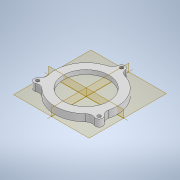
# Autodesk Inventor part: PalmClosure
Saved by Autodesk Inventor 2021 (Build 250183000, 183)
## iProperties
Created: 2026-04-22
Part Number: PalmClosure
Material: Generic
Document SubType Name: Modeling
Designer: Admin
Density: 1 g/cm^3
Appearance: Default
Author: Admin
Autodesk Inventor part; units mm, degrees
sketch "Sketch2" plane through (0, 0, 0) normal (0, 0, 1) x (1, 0, 0)
  line L0 (0, 6) -> (0, -1) projected
  line L1 (-26.4, 0) -> (4.4, 0) projected
  line L2 (0, -1) -> (0, 6) projected
  line L3 (-20, 0) -> (-22, 0)
  line L4 (-22, 0) -> (-22, 5)
  line L5 (-22, 5) -> (-16, 5)
  line L6 (-16, 5) -> (-16, 2)
  line L7 (-16, 2) -> (-18, 2)
  line L8 (-18, 2) -> (-18, 3)
  line L9 (-18, 3) -> (-20, 3)
  line L10 (-20, 3) -> (-20, 0)
  point P0 (0, 0)
  dimension "d33" = 22
  dimension "d34" = 16
  dimension "d35" = 2
  dimension "d36" = 2
  dimension "d37" = 5
  dimension "d38" = 3
  dimension "d39" = 2
  constraints: 16 end point, 6 perpendicular, 2 point on line, 1 vertical
  measures "d33" distance between parallel lines of L0 L4
  measures "d34" distance between parallel lines of L0 L6
  measures "d35" distance of L6.end L7.end
  measures "d36" distance of L8.end L9.end
  measures "d37" distance of L3.end L4.end
  measures "d38" distance between parallel lines of L1 L9
  measures "d39" distance between parallel lines of L1 L7
revolve "Revolution1" add sketch "Sketch2" angle 360 about axis through (0, -10, 0) along (0, 1, 0)
sketch "Sketch3" plane through (0, 5, 0) normal (0, 1, 0) x (1, 0, 0)
  circle A0 centre (0, 25) radius 2.5
  line L0 (0, 37.4) -> (0, -31.9) projected
  line L1 (2.5, 25) -> (2.5, 21.8575)
  line L2 (-2.5, 21.8575) -> (-2.5, 25)
  line L3 (30.8, 0) -> (-30.8, 0) projected
  circle A1 centre (0, 0) radius 22 projected
  dimension "d8" = 5
  dimension "d9" = 25
  constraints: 4 end point, 3 point on circle, 2 tangent, 1 centre point, 1 parallel, 1 point on line, 1 vertical
  measures "d8" diameter of A0
  measures "d9" distance from line of L3 A0.centre
extrude "Extrusion1" add sketch "Sketch3" against normal up to surface (5 mm away) contours A0 L0 | L1 A1 L0 A0 | L0 A0 | L0 A1 L2 A0
sketch "Sketch4" plane through (0, 5, -25) normal (0, 1, 0) x (1, 0, 0)
  arc A0 (2.5, 0) -> (-2.5, 0) centre (0, 0) ccw projected
  point P0 (0, -25)
  constraints: 1 coincident
hole "Hole1" at (0, 5, -25) direction (0, -1, 0) diameter 2.4 depth 26 clearance for "Countersunk Flat Head Screw ISO 2009/7046" size "M2" standard "ISO"
fillet "Fillet1" radius 5 2 edges at (-2.5, 2.5, -21.8575) (2.5, 2.5, -21.8575)
pattern_circular "Circular Pattern1" count 3 over 360 about axis through (0, -10, 0) along (0, 1, 0) of "Hole1", "Fillet1", "Extrusion1"
body "Solid1"
